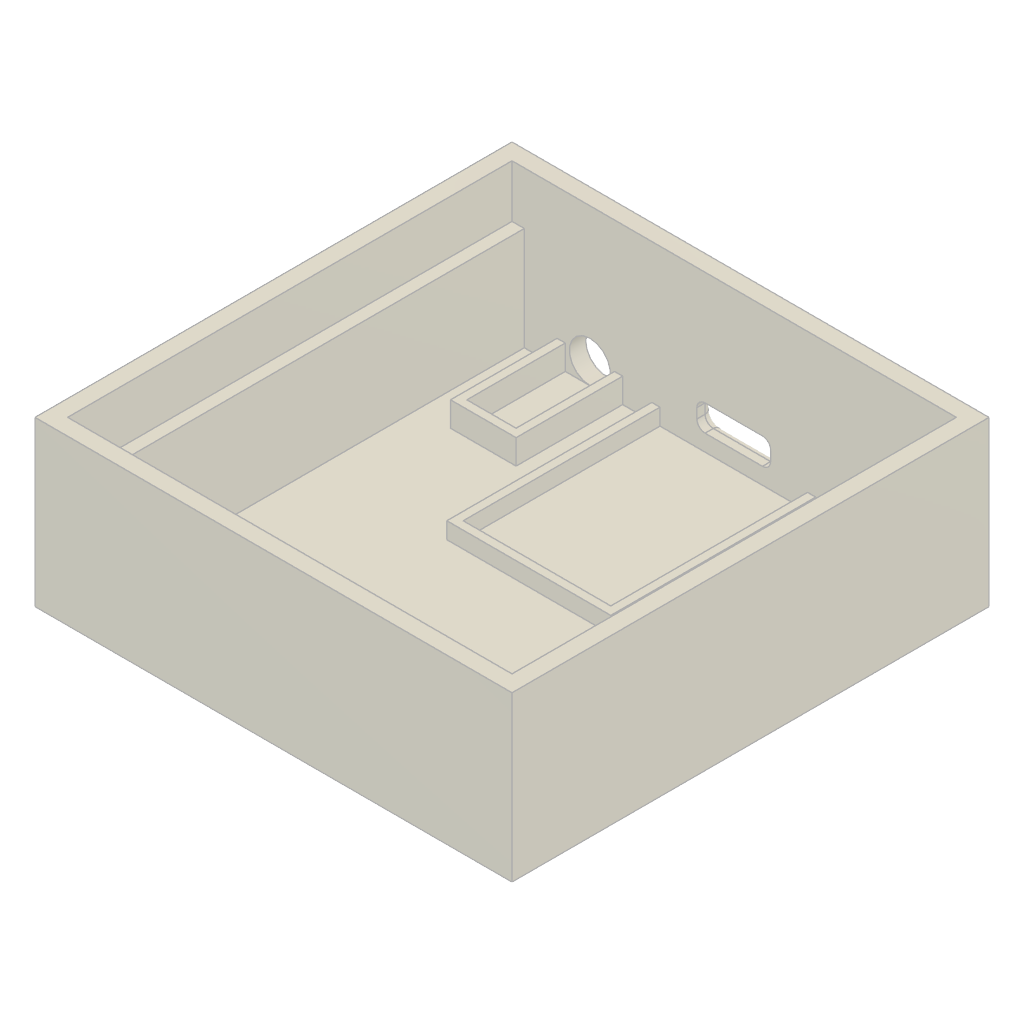
case (Autodesk Fusion 360 design; units mm, degrees)
part number: 2026-10-06-01-14-02-929
Autodesk Fusion 360 part; units mm, degrees
note: some values were not read from the file. Set by a fixed rule: which sketch regions a step uses.
sketch "Sketch1" plane through (0, 0, 0) normal (0, 1, 0) x (1, 0, 0)
  line L0 (0, 0) -> (54.2, 0)
  line L1 (54.2, 0) -> (54.2, 54.2)
  line L2 (54.2, 54.2) -> (0, 54.2)
  line L3 (0, 54.2) -> (0, 0)
  line L4 (-2, -2) -> (56.2, -2)
  line L5 (56.2, -2) -> (56.2, 56.2)
  line L6 (56.2, 56.2) -> (-2, 56.2)
  line L7 (-2, 56.2) -> (-2, -2)
  line L8 (1.5, 54.2) -> (1.5, 0)
  line L9 (52.7, 54.2) -> (52.7, 0)
  dimension "d1" = 54.2
  dimension "d2" = 54.2
  dimension "d3" = 2
  dimension "d15" = 1.5
  dimension "d16" = 1.5
  constraint horizontal L0
  constraint vertical L1
  constraint horizontal L2
  constraint vertical L3
  constraint coincident L0.start L3.end
  constraint coincident L2 L8.start
  constraint coincident L0 L8.end
  constraint perpendicular L0 L8
  constraint coincident L2 L9.start
  constraint coincident L0 L9.end
  constraint perpendicular L0 L9
  measures "d1" distance of L0.start L2.end
  measures "d2" distance of L1.end L2.end
  measures "d15" distance of L3 L8
  measures "d16" distance of L1 L9
extrude "Extrude3" add sketch "Sketch1" along normal blind 13.6 contours L0 L2 L3 L8 | L0 L1 L2 L9 makes body 1 at (52.7, 4.5333, -36.1333) makes body 2 at (0, 4.5333, -36.1333)
extrude "Extrude1" add sketch "Sketch1" along normal blind 1 contours L0 L2 L3 L8 | L0 L2 L8 L9 | L0 L1 L2 L9 bodies 1 2
extrude "Extrude2" add sketch "Sketch1" along normal blind 20 bodies 1
sketch "Sketch2" plane through (0, 1, 0) normal (0, 1, 0) x (-1, 0, 0)
  line L0 (-52.7, 0) -> (-52.7, -54.2)
  line L1 (-52.7, -54.2) -> (-1.5, -54.2)
  line L2 (-1.5, -54.2) -> (-1.5, 0)
  line L3 (-1.5, 0) -> (-52.7, 0)
  line L4 (-1.5, -54.2) -> (-52.7, -54.2) construction
  line L5 (-18.05, -54.2) -> (-36.05, -54.2)
  line L6 (-36.05, -54.2) -> (-36.05, -30.2)
  line L7 (-36.05, -30.2) -> (-18.05, -30.2)
  line L8 (-18.05, -30.2) -> (-18.05, -54.2)
  line L9 (-17.05, -54.2) -> (-17.05, -29.2)
  line L10 (-17.05, -29.2) -> (-37.05, -29.2)
  line L11 (-37.05, -29.2) -> (-37.05, -54.2)
  dimension "d18" = 24
  dimension "d19" = 18
  dimension "d20" = 16.55
  dimension "d21" = 16.65
  dimension "d22" = 1
  dimension "d23" = 1
  dimension "d24" = 1
  constraint coincident L1.end L2.start
  constraint coincident L0.end L1.start
  constraint horizontal L5
  constraint vertical L6
  constraint horizontal L7
  constraint vertical L8
  constraint coincident L4 L5.start
  constraint coincident L4 L9.start
  constraint perpendicular L4 L9
  constraint perpendicular L9 L10
  constraint coincident L4 L11.end
  constraint perpendicular L4 L11
  measures "d18" distance of L5 L7
  measures "d19" distance of L6 L8
  measures "d20" distance of L2 L8
  measures "d21" distance of L0 L6
  measures "d22" distance of L8 L9
  measures "d23" distance of L7 L10
  measures "d24" distance of L6 L11
extrude "Extrude4" add sketch "Sketch2" along normal blind 2 contours L1 L6 L7 L8 L9 L10 L11 bodies 1
sketch "Sketch3" plane through (0, 0, -56.2) normal (0, 0, -1) x (-1, 0, 0)
  line L0 (-56.2, 0) -> (2, 0)
  line L1 (2, 0) -> (2, 20)
  line L2 (2, 20) -> (-56.2, 20)
  line L3 (-56.2, 20) -> (-56.2, 0)
  line L4 (-31.55, 6.2) -> (-22.55, 6.2)
  line L5 (-22.55, 6.2) -> (-22.55, 3)
  line L6 (-22.55, 3) -> (-31.55, 3)
  line L7 (-31.55, 3) -> (-31.55, 6.2)
  circle A0 centre (-9.5, 3.5) radius 2.5
  dimension "d27" = 9
  dimension "d28" = 3.2
  dimension "d29" = 24.55
  dimension "d30" = 24.65
  dimension "d31" = 3
  dimension "d41" = 5
  dimension "d42" = 11.5
  dimension "d43" = 3.5
  constraint horizontal L4
  constraint vertical L5
  constraint horizontal L6
  constraint vertical L7
  measures "d27" distance of L4.start L4.end
  measures "d28" distance of L4.start L6.end
  measures "d29" distance of L1 L5
  measures "d30" distance of L3 L7
  measures "d31" distance of L0 L6
  measures "d41" diameter of A0
  measures "d42" distance of L1 A0.centre
  measures "d43" distance of L0 A0.centre
extrude "Extrude5" cut sketch "Sketch3" against normal up to surface (2 mm away) contours L4 L5 L6 L7 | A0 bodies 1
sketch "Sketch4" plane through (0, 1, 0) normal (0, 1, 0) x (-1, 0, 0)
  line L0 (-17.05, -29.2) -> (-17.05, -54.2)
  line L1 (-17.05, -54.2) -> (-9.5, -54.2)
  line L2 (-1.5, -54.2) -> (-1.5, 0)
  line L3 (-1.5, 0) -> (-52.7, 0)
  line L4 (-52.7, 0) -> (-52.7, -54.2)
  line L5 (-52.7, -54.2) -> (-37.05, -54.2)
  line L6 (-37.05, -54.2) -> (-37.05, -29.2)
  line L7 (-37.05, -29.2) -> (-17.05, -29.2)
  line L8 (-6.5, -54.2) -> (-6.5, -42.2)
  line L9 (-6.5, -42.2) -> (-12.5, -42.2)
  line L10 (-12.5, -42.2) -> (-12.5, -54.2)
  line L11 (-5.5, -54.2) -> (-5.5, -41.2)
  line L12 (-5.5, -41.2) -> (-13.5, -41.2)
  line L13 (-13.5, -41.2) -> (-13.5, -54.2)
  line L14 (-9.5, -54.2) -> (-1.5, -54.2)
  dimension "d34" = 6
  dimension "d35" = 12
  dimension "d36" = 1
  dimension "d39" = 4
  dimension "d40" = 3.55
  constraint coincident L1 L8.start
  constraint perpendicular L1 L8
  constraint perpendicular L8 L9
  constraint coincident L1 L10.end
  constraint perpendicular L1 L10
  measures "d34" distance of L8.end L9.end
  measures "d35" distance of L9.end L10.end
  measures "d39" distance of L2 L11
  measures "d40" distance of L0 L13
extrude "Extrude6" add sketch "Sketch4" along normal blind 3 contours L1 L8 L9 L10 L11 L12 L13 L14 bodies 1
fillet "Fillet1" radius 1 4 edges at (31.55, 6.2, -55.2) (22.55, 6.2, -55.2) (22.55, 3, -55.2) (31.55, 3, -55.2) on bodies 1
fillet "Fillet2" radius 1 8 edges at (22.8429, 5.9071, -56.2) (27.05, 6.2, -56.2) (31.2571, 5.9071, -56.2) (31.55, 4.6, -56.2) (31.2571, 3.2929, -56.2) (27.05, 3, -56.2) (22.8429, 3.2929, -56.2) (22.55, 4.6, -56.2) on bodies 1
equation "d9 = 20 mm - 6.4 mm"
equation "d23 = d22"
equation "d24 = d23"
